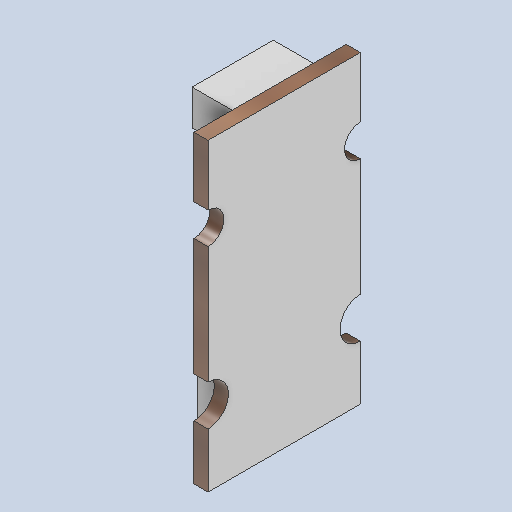
# Autodesk Inventor part: pcb_sensor
Saved by Autodesk Inventor 2026.1 (Build 301233020, 233B)
## iProperties
Created: 2026-01-07
Part Number: pcb_sensor
Material: Generico
Document SubType Name: Modeling
Designer: maxbu
Density: 1 g/cm^3
Appearance: Default
Categories: <MemberInstance><Categories><Category DisplayName="" Mnemonic="CABLEANDHARNESS" InternalName="e4a7e005-5e42-4d16-b293-125e7f0d0512"><Category DisplayName="" Mnemonic="CONNECTORS" InternalName="6f634eba-a678-4820-a31d-2c2d5ee6728e"><CategoryParameter DisplayName="" Mnemonic="REFDES" InternalName="c3740e8c-60ab-4d5d-8584-52b73222f2f0"/><Category DisplayName="" Mnemonic="DISCRETEWIRE" InternalName="9a3407de-09b2-4cdb-8c40-9708d5144a28"/></Category></Category></Categories><FamilyTemplate><FamilyTemplateParameters></FamilyTemplateParameters></FamilyTemplate><CategoryParameterMap><ParamToTemplateMap><ParamToTemplate CategoryParameter="//CategoryParameter[@InternalName='c3740e8c-60ab-4d5d-8584-52b73222f2f0']" ConstantValue=""/></ParamToTemplateMap></CategoryParameterMap></MemberInstance>
GlobalPropertyList: <PropertyList/>
Author: maxbu
Autodesk Inventor part; units mm, degrees
ref_plane "YZ Plane" through (0, 0, 0) normal (1, 0, 0) x (0, 1, 0)
ref_plane "XZ Plane" through (0, 0, 0) normal (0, 1, 0) x (-1, 0, 0)
ref_plane "XY Plane" through (0, 0, 0) normal (0, 0, 1) x (1, 0, 0)
sketch "Schizzo1" plane through (0, 0, 0) normal (1, 0, 0) x (0, 1, 0)
  line L0 (-0.0001, 0) -> (60.9599, 0) construction
  line L1 (60.9599, 0) -> (60.9599, -45.72) construction
  line L2 (60.9599, -45.72) -> (-0.0001, -45.72) construction
  line L3 (-0.0001, -45.72) -> (-0.0001, 0) construction
  line L4 (9.845, -10.5438) -> (53.045, -10.5438)
  line L5 (53.045, -10.5438) -> (53.045, -32.1438)
  line L6 (53.045, -32.1438) -> (9.845, -32.1438)
  line L7 (9.845, -32.1438) -> (9.845, -10.5438)
  circle A0 centre (42.2451, -10.5438) radius 1.17
  circle A1 centre (42.2451, -10.5438) radius 2.25
  line L8 (53.045, -21.3438) -> (9.845, -21.3438) construction
  line L9 (-0.0001, 0) -> (9.845, -10.5438) construction
  circle A2 centre (20.4651, -10.5438) radius 2.88
  circle A3 centre (42.2451, -32.1438) radius 1.17
  circle A4 centre (42.2451, -32.1438) radius 2.25
  circle A5 centre (20.4651, -32.1438) radius 2.88
  point P0 (0, 0)
  point P1 (44.4951, -10.5438)
  point P2 (39.9951, -10.5438)
  point P3 (23.3451, -10.5438)
  point P4 (17.5851, -10.5438)
  point P5 (17.5851, -32.1438)
  point P6 (23.3451, -32.1438)
  point P7 (39.9951, -32.1438)
  point P8 (44.4951, -32.1438)
  dimension "d1" = 9.845
  dimension "d2" = 10.5438
  dimension "d3" = 43.2
  dimension "d4" = 21.6
  dimension "d5" = 2.34
  dimension "d6" = 4.5
  dimension "d7" = 32.4001
  dimension "d8" = 5.76
  dimension "d9" = 10.6201
  constraints: 14 end point, 6 centre point, 3 symmetric about line, 2 coincident, 2 midpoint, 2 parallel, 2 point on line, 1 horizontal, 1 perpendicular, 5 other
  measures "d1" horizontal distance of point (0, 0) L4.start
  measures "d2" vertical distance of point (0, 0) L4.start
  measures "d3" distance of L4.start L4.end
  measures "d4" distance of L6.end L4.start
  measures "d5" diameter of A0
  measures "d6" diameter of A1
  measures "d7" distance of L4.start A0.centre
  measures "d8" diameter of A2
  measures "d9" distance of L4.start A2.centre
extrude "Estrusione1" add sketch "Schizzo1" along normal blind 2 contours L4 L5 L6 A4 A5 L7 A2 A1
sketch "Schizzo2" plane through (0, 0, 0) normal (-1, 0, 0) x (0, 0, 1)
  line L0 (-26.5008, 30.0634) -> (-16.806, 30.0634)
  line L1 (-16.806, 30.0634) -> (-16.806, 26.0063)
  line L2 (-16.806, 26.0063) -> (-26.5008, 26.0063)
  line L3 (-26.5008, 26.0063) -> (-26.5008, 30.0634)
  line L4 (-27.2384, 41.1281) -> (-16.121, 41.1281)
  line L5 (-16.121, 41.1281) -> (-16.121, 37.0183)
  line L6 (-16.121, 37.0183) -> (-27.2384, 37.0183)
  line L7 (-27.2384, 37.0183) -> (-27.2384, 41.1281)
  line L8 (-15.0649, 38.4935) -> (-11.9811, 38.4935)
  line L9 (-11.9811, 38.4935) -> (-11.9811, 36.8522)
  line L10 (-11.9811, 36.8522) -> (-15.0649, 36.8522)
  line L11 (-15.0649, 36.8522) -> (-15.0649, 38.4935)
  line L12 (-30.4377, 39.5092) -> (-28.877, 39.5092)
  line L13 (-28.877, 39.5092) -> (-28.877, 36.484)
  line L14 (-28.877, 36.484) -> (-30.4377, 36.484)
  line L15 (-30.4377, 36.484) -> (-30.4377, 39.5092)
  point P0 (0, 0)
  constraints: 32 end point, 8 parallel, 4 horizontal, 4 perpendicular
extrude "Estrusione2" add sketch "Schizzo2" along normal blind 1
sketch "Schizzo3" plane through (0, 0, 0) normal (-1, 0, 0) x (0, 0, 1)
  line L0 (-29.892, 45.1373) -> (-28.5794, 45.1373)
  line L1 (-28.5794, 45.1373) -> (-28.5794, 44.5496)
  line L2 (-28.5794, 44.5496) -> (-29.892, 44.5496)
  line L3 (-29.892, 44.5496) -> (-29.892, 45.1373)
  line L4 (-29.892, 44.1186) -> (-28.4226, 44.1186)
  line L5 (-28.4226, 44.1186) -> (-28.4226, 43.5897)
  line L6 (-28.4226, 43.5897) -> (-29.892, 43.5897)
  line L7 (-29.892, 43.5897) -> (-29.892, 44.1186)
  line L8 (-29.7548, 43.0607) -> (-28.5794, 43.0607)
  line L9 (-28.5794, 43.0607) -> (-28.5794, 42.375)
  line L10 (-28.5794, 42.375) -> (-29.7548, 42.375)
  line L11 (-29.7548, 42.375) -> (-29.7548, 43.0607)
  line L12 (-29.892, 41.0624) -> (-28.4226, 41.0624)
  line L13 (-28.4226, 41.0624) -> (-28.4226, 40.4943)
  line L14 (-28.4226, 40.4943) -> (-29.892, 40.4943)
  line L15 (-29.892, 40.4943) -> (-29.892, 41.0624)
  line L16 (-30.4377, 36.484) -> (-30.4377, 39.5092) projected
  line L17 (-31.1227, 38.3814) -> (-30.4377, 38.3814)
  line L18 (-30.4377, 38.3814) -> (-30.4377, 37.5933)
  line L19 (-30.4377, 37.5933) -> (-31.1227, 37.5933)
  line L20 (-31.1227, 37.5933) -> (-31.1227, 38.3814)
  line L21 (-28.877, 39.5092) -> (-28.877, 36.484) projected
  line L22 (-28.877, 39.2854) -> (-28.4226, 39.2854)
  line L23 (-28.4226, 39.2854) -> (-28.4226, 38.9377)
  line L24 (-28.4226, 38.9377) -> (-28.877, 38.9377)
  line L25 (-28.877, 38.9377) -> (-28.877, 39.2854)
  line L26 (-28.877, 37.2224) -> (-27.9702, 37.2224)
  line L27 (-27.9702, 37.2224) -> (-27.9702, 36.782)
  line L28 (-27.9702, 36.782) -> (-28.877, 36.782)
  line L29 (-28.877, 36.782) -> (-28.877, 37.2224)
  line L30 (-27.2384, 41.1281) -> (-16.121, 41.1281) projected
  line L31 (-17.0292, 43.0607) -> (-16.4497, 43.0607)
  line L32 (-16.4497, 43.0607) -> (-16.4497, 41.1281)
  line L33 (-16.4497, 41.1281) -> (-17.0292, 41.1281)
  line L34 (-17.0292, 41.1281) -> (-17.0292, 43.0607)
  line L35 (-18.42, 43.0607) -> (-17.8869, 43.0607)
  line L36 (-17.8869, 43.0607) -> (-17.8869, 41.1281)
  line L37 (-17.8869, 41.1281) -> (-18.42, 41.1281)
  line L38 (-18.42, 41.1281) -> (-18.42, 43.0607)
  line L39 (-19.7876, 43.0607) -> (-19.185, 43.0607)
  line L40 (-19.185, 43.0607) -> (-19.185, 41.1281)
  line L41 (-19.185, 41.1281) -> (-19.7876, 41.1281)
  line L42 (-19.7876, 41.1281) -> (-19.7876, 43.0607)
  line L43 (-21.1553, 42.6195) -> (-20.7148, 42.6195)
  line L44 (-20.7148, 42.6195) -> (-20.7148, 41.1281)
  line L45 (-20.7148, 41.1281) -> (-21.1553, 41.1281)
  line L46 (-21.1553, 41.1281) -> (-21.1553, 42.6195)
  line L47 (-22.5924, 43.192) -> (-22.1056, 43.192)
  line L48 (-22.1056, 43.192) -> (-22.1056, 41.1281)
  line L49 (-22.1056, 41.1281) -> (-22.5924, 41.1281)
  line L50 (-22.5924, 41.1281) -> (-22.5924, 43.192)
  line L51 (-23.9369, 43.192) -> (-23.3806, 43.192)
  line L52 (-23.3806, 43.192) -> (-23.3806, 41.1281)
  line L53 (-23.3806, 41.1281) -> (-23.9369, 41.1281)
  line L54 (-23.9369, 41.1281) -> (-23.9369, 43.192)
  line L55 (-25.3045, 43.192) -> (-24.6323, 43.192)
  line L56 (-24.6323, 43.192) -> (-24.6323, 41.1281)
  line L57 (-24.6323, 41.1281) -> (-25.3045, 41.1281)
  line L58 (-25.3045, 41.1281) -> (-25.3045, 43.192)
  line L59 (-26.6258, 43.192) -> (-26.1853, 43.192)
  line L60 (-26.1853, 43.192) -> (-26.1853, 41.1281)
  line L61 (-26.1853, 41.1281) -> (-26.6258, 41.1281)
  line L62 (-26.6258, 41.1281) -> (-26.6258, 43.192)
  line L63 (-26.6258, 35.1826) -> (-26.1853, 35.1826)
  line L64 (-26.1853, 35.1826) -> (-26.1853, 36.782)
  line L65 (-26.1853, 36.782) -> (-26.6258, 36.782)
  line L66 (-26.6258, 36.782) -> (-26.6258, 35.1826)
  line L67 (-27.2384, 37.0183) -> (-16.121, 37.0183) projected
  line L68 (-25.3045, 35.3448) -> (-24.6323, 35.3448)
  line L69 (-24.6323, 35.3448) -> (-24.6323, 37.0183)
  line L70 (-24.6323, 37.0183) -> (-25.3045, 37.0183)
  line L71 (-25.3045, 37.0183) -> (-25.3045, 35.3448)
  line L72 (-23.9369, 35.3448) -> (-23.3806, 35.3448)
  line L73 (-23.3806, 35.3448) -> (-23.3806, 37.0183)
  line L74 (-23.3806, 37.0183) -> (-23.9369, 37.0183)
  line L75 (-23.9369, 37.0183) -> (-23.9369, 35.3448)
  line L76 (-22.5924, 35.3448) -> (-22.1056, 35.3448)
  line L77 (-22.1056, 35.3448) -> (-22.1056, 37.0183)
  line L78 (-22.1056, 37.0183) -> (-22.5924, 37.0183)
  line L79 (-22.5924, 37.0183) -> (-22.5924, 35.3448)
  line L80 (-21.1553, 35.3448) -> (-20.7148, 35.3448)
  line L81 (-20.7148, 35.3448) -> (-20.7148, 37.0183)
  line L82 (-20.7148, 37.0183) -> (-21.1553, 37.0183)
  line L83 (-21.1553, 37.0183) -> (-21.1553, 35.3448)
  line L84 (-19.7876, 35.3448) -> (-19.185, 35.3448)
  line L85 (-19.185, 35.3448) -> (-19.185, 37.0183)
  line L86 (-19.185, 37.0183) -> (-19.7876, 37.0183)
  line L87 (-19.7876, 37.0183) -> (-19.7876, 35.3448)
  line L88 (-18.42, 35.3448) -> (-17.6087, 35.3448)
  line L89 (-17.6087, 35.3448) -> (-17.6087, 36.782)
  line L90 (-17.6087, 36.782) -> (-18.42, 36.782)
  line L91 (-18.42, 36.782) -> (-18.42, 35.3448)
  line L92 (-17.0292, 35.3448) -> (-16.4497, 35.3448)
  line L93 (-16.4497, 35.3448) -> (-16.4497, 37.0183)
  line L94 (-16.4497, 37.0183) -> (-17.0292, 37.0183)
  line L95 (-17.0292, 37.0183) -> (-17.0292, 35.3448)
  line L96 (-15.0649, 38.4935) -> (-11.9811, 38.4935) projected
  line L97 (-14.7112, 39.7221) -> (-14.2476, 39.7221)
  line L98 (-14.2476, 39.7221) -> (-14.2476, 38.4935)
  line L99 (-14.2476, 38.4935) -> (-14.7112, 38.4935)
  line L100 (-14.7112, 38.4935) -> (-14.7112, 39.7221)
  line L101 (-12.7872, 39.7221) -> (-12.2309, 39.7221)
  line L102 (-12.2309, 39.7221) -> (-12.2309, 38.6828)
  line L103 (-12.2309, 38.6828) -> (-12.7872, 38.6828)
  line L104 (-12.7872, 38.6828) -> (-12.7872, 39.7221)
  line L105 (-13.8767, 36.782) -> (-13.135, 36.782)
  line L106 (-13.135, 36.782) -> (-13.135, 35.5998)
  line L107 (-13.135, 35.5998) -> (-13.8767, 35.5998)
  line L108 (-13.8767, 35.5998) -> (-13.8767, 36.782)
  line L109 (-14.7112, 42.6195) -> (-13.135, 42.6195)
  line L110 (-13.135, 42.6195) -> (-13.135, 42.16)
  line L111 (-13.135, 42.16) -> (-14.7112, 42.16)
  line L112 (-14.7112, 42.16) -> (-14.7112, 42.6195)
  line L113 (-14.7112, 41.3948) -> (-13.135, 41.3948)
  line L114 (-13.135, 41.3948) -> (-13.135, 40.7784)
  line L115 (-13.135, 40.7784) -> (-14.7112, 40.7784)
  line L116 (-14.7112, 40.7784) -> (-14.7112, 41.3948)
  line L117 (-25.3045, 47.2163) -> (-24.4544, 47.2163)
  line L118 (-24.4544, 47.2163) -> (-24.4544, 44.8435)
  line L119 (-24.4544, 44.8435) -> (-25.3045, 44.8435)
  line L120 (-25.3045, 44.8435) -> (-25.3045, 47.2163)
  line L121 (-23.1146, 46.993) -> (-22.349, 46.993)
  line L122 (-22.349, 46.993) -> (-22.349, 44.8435)
  line L123 (-22.349, 44.8435) -> (-23.1146, 44.8435)
  line L124 (-23.1146, 44.8435) -> (-23.1146, 46.993)
  line L125 (-21.1553, 46.993) -> (-19.7876, 46.993)
  line L126 (-19.7876, 46.993) -> (-19.7876, 44.5496)
  line L127 (-19.7876, 44.5496) -> (-21.1553, 44.5496)
  line L128 (-21.1553, 44.5496) -> (-21.1553, 46.993)
  line L129 (-18.6485, 47.4676) -> (-17.8869, 47.4676)
  line L130 (-17.8869, 47.4676) -> (-17.8869, 44.5496)
  line L131 (-17.8869, 44.5496) -> (-18.6485, 44.5496)
  line L132 (-18.6485, 44.5496) -> (-18.6485, 47.4676)
  line L133 (-16.806, 30.0634) -> (-26.5008, 30.0634) projected
  line L134 (-26.1853, 32.3721) -> (-25.4884, 32.3721)
  line L135 (-25.4884, 32.3721) -> (-25.4884, 30.0634)
  line L136 (-25.4884, 30.0634) -> (-26.1853, 30.0634)
  line L137 (-26.1853, 30.0634) -> (-26.1853, 32.3721)
  line L138 (-24.6323, 32.3721) -> (-23.9369, 32.3721)
  line L139 (-23.9369, 32.3721) -> (-23.9369, 30.0634)
  line L140 (-23.9369, 30.0634) -> (-24.6323, 30.0634)
  line L141 (-24.6323, 30.0634) -> (-24.6323, 32.3721)
  line L142 (-23.1146, 32.3721) -> (-22.7318, 32.3721)
  line L143 (-22.7318, 32.3721) -> (-22.7318, 30.0634)
  line L144 (-22.7318, 30.0634) -> (-23.1146, 30.0634)
  line L145 (-23.1146, 30.0634) -> (-23.1146, 32.3721)
  line L146 (-21.8355, 32.3721) -> (-21.1553, 32.3721)
  line L147 (-21.1553, 32.3721) -> (-21.1553, 30.0634)
  line L148 (-21.1553, 30.0634) -> (-21.8355, 30.0634)
  line L149 (-21.8355, 30.0634) -> (-21.8355, 32.3721)
  line L150 (-20.7148, 32.3721) -> (-19.7876, 32.3721)
  line L151 (-19.7876, 32.3721) -> (-19.7876, 30.0634)
  line L152 (-19.7876, 30.0634) -> (-20.7148, 30.0634)
  line L153 (-20.7148, 30.0634) -> (-20.7148, 32.3721)
  line L154 (-19.185, 32.3721) -> (-18.6485, 32.3721)
  line L155 (-18.6485, 32.3721) -> (-18.6485, 30.0634)
  line L156 (-18.6485, 30.0634) -> (-19.185, 30.0634)
  line L157 (-19.185, 30.0634) -> (-19.185, 32.3721)
  line L158 (-17.6087, 32.6436) -> (-17.0292, 32.6436)
  line L159 (-17.0292, 32.6436) -> (-17.0292, 30.2248)
  line L160 (-17.0292, 30.2248) -> (-17.6087, 30.2248)
  line L161 (-17.6087, 30.2248) -> (-17.6087, 32.6436)
  line L162 (-25.8368, 25.7036) -> (-25.3045, 25.7036)
  line L163 (-25.3045, 25.7036) -> (-25.3045, 24.0363)
  line L164 (-25.3045, 24.0363) -> (-25.8368, 24.0363)
  line L165 (-25.8368, 24.0363) -> (-25.8368, 25.7036)
  line L166 (-26.5008, 26.0063) -> (-16.806, 26.0063) projected
  line L167 (-24.6323, 26.0063) -> (-23.9369, 26.0063)
  line L168 (-23.9369, 26.0063) -> (-23.9369, 24.0363)
  line L169 (-23.9369, 24.0363) -> (-24.6323, 24.0363)
  line L170 (-24.6323, 24.0363) -> (-24.6323, 26.0063)
  line L171 (-23.3806, 26.0063) -> (-22.5924, 26.0063)
  line L172 (-22.5924, 26.0063) -> (-22.5924, 24.0363)
  line L173 (-22.5924, 24.0363) -> (-23.3806, 24.0363)
  line L174 (-23.3806, 24.0363) -> (-23.3806, 26.0063)
  line L175 (-21.9496, 26.0063) -> (-21.279, 26.0063)
  line L176 (-21.279, 26.0063) -> (-21.279, 24.0363)
  line L177 (-21.279, 24.0363) -> (-21.9496, 24.0363)
  line L178 (-21.9496, 24.0363) -> (-21.9496, 26.0063)
  line L179 (-20.4715, 26.0063) -> (-19.7876, 26.0063)
  line L180 (-19.7876, 26.0063) -> (-19.7876, 24.0363)
  line L181 (-19.7876, 24.0363) -> (-20.4715, 24.0363)
  line L182 (-20.4715, 24.0363) -> (-20.4715, 26.0063)
  line L183 (-19.0499, 26.0063) -> (-18.42, 26.0063)
  line L184 (-18.42, 26.0063) -> (-18.42, 24.0363)
  line L185 (-18.42, 24.0363) -> (-19.0499, 24.0363)
  line L186 (-19.0499, 24.0363) -> (-19.0499, 26.0063)
  line L187 (-17.745, 26.0063) -> (-17.0292, 26.0063)
  line L188 (-17.0292, 26.0063) -> (-17.0292, 24.0363)
  line L189 (-17.0292, 24.0363) -> (-17.745, 24.0363)
  line L190 (-17.745, 24.0363) -> (-17.745, 26.0063)
  line L191 (-23.3806, 21.8599) -> (-22.5924, 21.8599)
  line L192 (-22.5924, 21.8599) -> (-22.5924, 18.1276)
  line L193 (-22.5924, 18.1276) -> (-23.3806, 18.1276)
  line L194 (-23.3806, 18.1276) -> (-23.3806, 21.8599)
  line L195 (-20.4715, 21.4711) -> (-19.7876, 21.4711)
  line L196 (-19.7876, 21.4711) -> (-19.7876, 18.7886)
  line L197 (-19.7876, 18.7886) -> (-20.4715, 18.7886)
  line L198 (-20.4715, 18.7886) -> (-20.4715, 21.4711)
  point P0 (0, 0)
  constraints: 384 end point, 111 point on line, 96 parallel, 48 horizontal, 48 perpendicular
extrude "Estrusione3" add sketch "Schizzo3" along normal blind 0.2
sketch "Schizzo4" plane through (0, 0, 0) normal (-1, 0, 0) x (0, 0, 1)
  line L0 (-26.9076, 51.8927) -> (-17.2922, 51.8927)
  line L1 (-17.2922, 51.8927) -> (-17.2922, 48.4343)
  line L2 (-17.2922, 48.4343) -> (-26.9076, 48.4343)
  line L3 (-26.9076, 48.4343) -> (-26.9076, 51.8927)
  line L4 (-27.7984, 52.7311) -> (-16.2703, 52.7311)
  line L5 (-16.2703, 52.7311) -> (-16.2703, 47.7269)
  line L6 (-16.2703, 47.7269) -> (-27.7984, 47.7269)
  line L7 (-27.7984, 47.7269) -> (-27.7984, 52.7311)
  line L8 (-10.5438, 9.845) -> (-32.1438, 9.845) projected
  line L9 (-26.2755, 18.1752) -> (-17.0209, 18.1752)
  line L10 (-17.0209, 18.1752) -> (-17.0209, 9.845)
  line L11 (-17.0209, 9.845) -> (-26.2755, 9.845)
  line L12 (-26.2755, 9.845) -> (-26.2755, 18.1752)
  line L13 (-23.422, 14.0101) -> (-20.0286, 14.0101)
  line L14 (-20.0286, 14.0101) -> (-20.0286, 9.845)
  line L15 (-20.0286, 9.845) -> (-23.422, 9.845)
  line L16 (-23.422, 9.845) -> (-23.422, 14.0101)
  line L17 (-26.2755, 10.1788) -> (-23.422, 10.1788)
  line L18 (-20.0286, 10.1788) -> (-17.0209, 10.1788)
  point P0 (0, 0)
  constraints: 36 end point, 8 parallel, 8 point on line, 5 perpendicular, 4 horizontal
extrude "Estrusione4" add sketch "Schizzo4" along normal blind 6 contours L4 L5 L6 L7 | L18 L14 L13 L16 L17 L12 L9 L10
scale "Scala1" factors (0.5, 0.5, 0.5) then translate (-1.5, 9.0876, -10.8241) bodies 1
